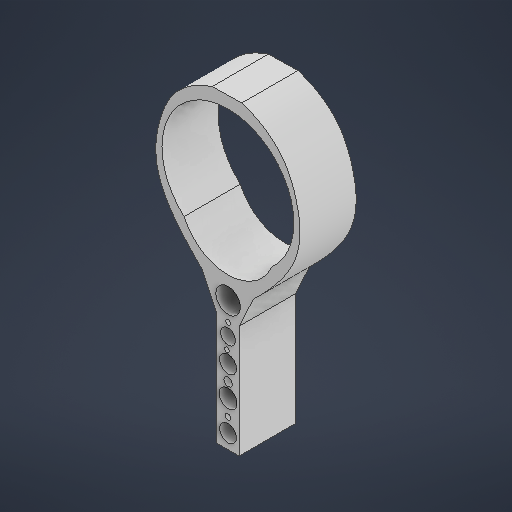
# Autodesk Inventor part: Michálek
Saved by Autodesk Inventor 2026.1 (Build 301233000, 233)
## iProperties
Created: 2026-05-13
Part Number: Michálek
Material: Všeobecné
Document SubType Name: Sheet Metal
Designer: jmichalek
Density: 1 g/cm^3
Sheet Metal Rule: Výchozí_mm
Appearance: Výchozí
Author: jmichalek
Autodesk Inventor part; units mm, degrees
ref_plane "YZ Plane" through (0, 0, 0) normal (1, 0, 0) x (0, 1, 0)
ref_plane "XZ Plane" through (0, 0, 0) normal (0, 1, 0) x (-1, 0, 0)
ref_plane "XY Plane" through (0, 0, 0) normal (0, 0, 1) x (1, 0, 0)
sketch "Náčrt1" plane through (0, 0, 0) normal (0, 0, 1) x (1, 0, 0)
  line L0 (7.7954, 20) -> (11.7954, 20)
  line L1 (11.7954, 20) -> (11.7954, 0)
  line L2 (11.7954, 0) -> (7.7954, 0)
  line L3 (7.7954, 20) -> (11.7954, 20)
  line L4 (7.7954, 20) -> (7.7954, 0)
  line L5 (7.7954, 20) -> (5.2597, 25.4378)
  line L6 (7.7954, 20) -> (13.7954, 20) construction
  line L7 (11.7954, 20) -> (14.3311, 25.4378)
  line L8 (5.2597, 25.4378) -> (14.3311, 25.4378)
  line L9 (5.2597, 25.4378) -> (25.2597, 25.4378) construction
  line L10 (5.2597, 25.4378) -> (0.8928, 29.7251) construction
  line L11 (0.8928, 29.7251) -> (-3.31, 35.4164) construction
  line L12 (-3.31, 35.4164) -> (-3.31, 41.4579) construction
  line L13 (-3.31, 41.4579) -> (-1.9091, 46.5363) construction
  line L14 (-1.9091, 46.5363) -> (-0.1079, 50.1955) construction
  spline S0 degree 4 poles (5.2597, 25.4378) (0.8928, 29.7251) (-3.31, 35.4164) (-3.31, 41.4579) (-1.9091, 46.5363) (-0.1079, 50.1955) (2.6266, 52.547) (5.0575, 53.8222) (6.9978, 54.5237) knots 1 1 1 1 1 2 3 4 5 5.773932 5.773932 5.773932 5.773932 5.773932
  line L15 (14.3311, 25.4378) -> (18.698, 29.7251) construction
  line L16 (18.698, 29.7251) -> (22.9008, 35.4164) construction
  line L17 (22.9008, 35.4164) -> (22.9008, 41.4579) construction
  line L18 (22.9008, 41.4579) -> (21.4998, 46.5363) construction
  line L19 (21.4998, 46.5363) -> (19.6839, 50.2255) construction
  spline S1 degree 4 poles (14.3311, 25.4378) (18.698, 29.7251) (22.9008, 35.4164) (22.9008, 41.4579) (21.4998, 46.5363) (19.6839, 50.2255) (16.903, 52.5993) (14.4056, 53.8886) (12.2745, 54.6371) knots 1 1 1 1 1 2 3 4 5 5.804825 5.804825 5.804825 5.804825 5.804825
  circle A0 centre (9.7954, 40.775) radius 11.7285
  circle A1 centre (9.7954, 35.4164) radius 8.5006
  line L20 (6.9978, 54.5237) -> (12.2745, 54.6371)
  line L21 (-0.1079, 50.1955) -> (2.6266, 52.547) construction
  line L22 (2.6266, 52.547) -> (5.0575, 53.8222) construction
  line L23 (5.0575, 53.8222) -> (6.9978, 54.5237) construction
  line L24 (19.6839, 50.2255) -> (16.903, 52.5993) construction
  line L25 (16.903, 52.5993) -> (14.4056, 53.8886) construction
  line L26 (14.4056, 53.8886) -> (12.2745, 54.6371) construction
  point P0 (0, 0)
  point P1 (17.5805, 32.0029)
  point P2 (2.0102, 32.0029)
  dimension "d0" = 20
  dimension "d1" = 4
  dimension "d2" = 20
  dimension "d3" = 90
  dimension "d4" = 6
  dimension "d5" = 115
  dimension "d6" = 6
  constraints: 22 end point, 4 horizontal, 2 centre point, 2 vertical, 1 collinear, 1 equal length, 1 perpendicular, 6 other
  measures "d0" distance of L2.end L0.start
  measures "d1" distance of L0.start L0.end
  measures "d2" distance of L0.end L1.end
  measures "d3" angle of L0 L1
  measures "d4" distance of L0.start L5.end
  measures "d5" angle of L6 L5
  measures "d6" distance of L0.end L7.end
extrude "Vysunutí1" add sketch "Náčrt1" along normal blind 10
sketch "Náčrt2" plane through (0, 0, 0) normal (0, 0, -1) x (-1, 0, 0)
  circle A0 centre (-9.8245, 23.0004) radius 2.1795
  circle A1 centre (-9.8245, 17.4347) radius 1.3411
  circle A2 centre (-9.8245, 13.1961) radius 1.5221
  circle A3 centre (-9.8245, 7.9037) radius 1.6007
  circle A4 centre (-9.8245, 2.5411) radius 1.4987
  circle A5 centre (-9.8245, 5.0625) radius 0.4961
  circle A6 centre (-9.8245, 10.4486) radius 0.7441
  circle A7 centre (-9.6054, 15.2678) radius 0.4167
  circle A8 centre (-9.8245, 19.6263) radius 0.4332
  point P0 (0, 0)
  constraints: 9 centre point
extrude "Vysunutí2" cut sketch "Náčrt2" against normal blind 10
equation "\"PoloměrOhybu\" = Tloušťka"
equation "\"ŠířkaVýštipu\" = Tloušťka"
equation "\"HloubkaVýštipu\" = 0.5 * Tloušťka"
equation "\"VelikostRohovéhoVýštipu\" = 4 * Tloušťka"
equation "\"MinimálníZbytek\" = 2 * Tloušťka"
equation "\"PřechodovýPoloměr\" = PoloměrOhybu"
equation "\"VelikostJacobihoPoloměru\" = PoloměrOhybu"
equation "\"VelikostMezery\" = Tloušťka"
equation "\"Tloušťka\" = 0.5"
